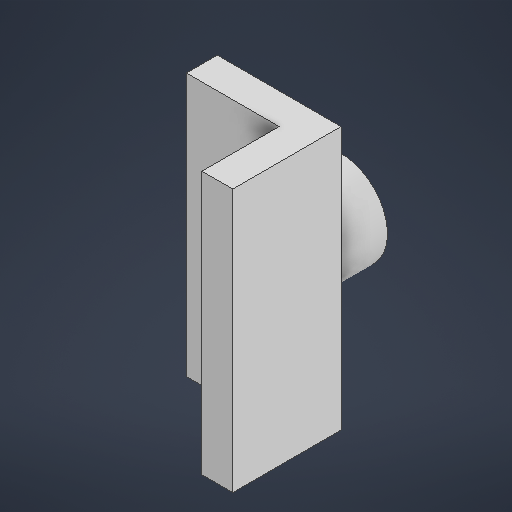
# Autodesk Inventor part: 开关
Saved by Autodesk Inventor 2025 (Build 290162000, 162)
## iProperties
Created: 2025-11-04
Part Number: 开关
Material: 常规
Document SubType Name: Modeling
Designer: HZD
Density: 1 g/cm^3
Appearance: 默认
Author: HZD
Autodesk Inventor part; units mm, degrees
ref_plane "YZ Plane" through (0, 0, 0) normal (1, 0, 0) x (0, 1, 0)
ref_plane "XZ Plane" through (0, 0, 0) normal (0, 1, 0) x (-1, 0, 0)
ref_plane "XY Plane" through (0, 0, 0) normal (0, 0, 1) x (1, 0, 0)
sketch "草图1" plane through (0, 0, 0) normal (0, 0, 1) x (1, 0, 0)
  line L0 (2, -4.25) -> (-2, -4.25)
  line L1 (-2, -4.25) -> (-2, 4.25)
  line L2 (-2, 4.25) -> (2, 4.25)
  line L3 (2, 4.25) -> (2, -4.25)
  line L4 (2, -4.25) -> (-2, 4.25) construction
  line L5 (-2, -4.25) -> (2, 4.25) construction
  point P0 (0, 0)
  dimension "d0" = 8.5
  dimension "d1" = 4
  constraints: 12 end point, 2 midpoint, 2 parallel, 1 horizontal, 1 perpendicular
  measures "d0" distance of L2.end L0.start
  measures "d1" distance between parallel lines of L1 L3
extrude "拉伸1" add sketch "草图1" along normal blind 1
sketch "草图2" plane through (0, 0, 1) normal (0, 0, 1) x (1, 0, 0)
  line L0 (2, 4.25) -> (-2, 4.25) projected
  line L1 (-2, -4.25) -> (2, -4.25) projected
  line L2 (1, 4.25) -> (2, 4.25)
  line L3 (2, 4.25) -> (2, -4.25)
  line L4 (2, -4.25) -> (1, -4.25)
  line L5 (1, -4.25) -> (1, 4.25)
  point P0 (0, 0)
  dimension "d4" = 1
  constraints: 8 end point, 2 parallel, 1 horizontal, 1 perpendicular, 1 point on line
  measures "d4" distance between parallel lines of L5 L3
extrude "拉伸2" add sketch "草图2" along normal blind 2.5
sketch "草图3" plane through (0, 0, 0) normal (0, 0, -1) x (-1, 0, 0)
  circle A0 centre (0, 0) radius 1.5
  dimension "d7" = 3
  constraints: 1 centre point, 1 coincident
  measures "d7" diameter of A0
extrude "拉伸3" add sketch "草图3" along normal blind 2
